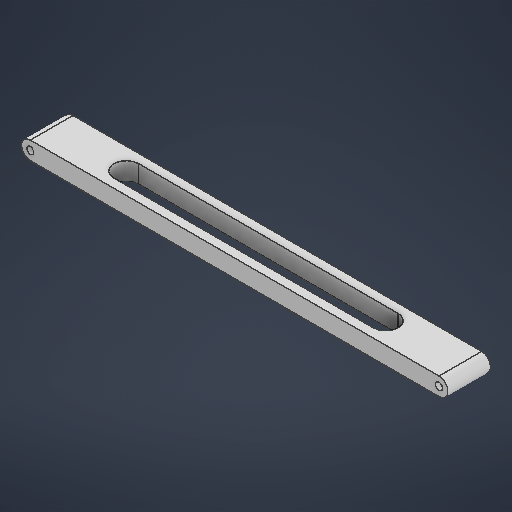
# Autodesk Inventor part: barraBrazo2
Saved by Autodesk Inventor 2027.1 (Build 311270010, 270A)
## iProperties
Created: 2026-11-02
Part Number: barraBrazo2
Material: Genérico
Document SubType Name: Modeling
Designer: MANGEL
Density: 1 g/cm^3
Appearance: Valor por defecto
Author: MANGEL
Autodesk Inventor part; units mm, degrees
ref_plane "YZ Plane" through (0, 0, 0) normal (1, 0, 0) x (0, 1, 0)
ref_plane "XZ Plane" through (0, 0, 0) normal (0, 1, 0) x (-1, 0, 0)
ref_plane "XY Plane" through (0, 0, 0) normal (0, 0, 1) x (1, 0, 0)
sketch "Boceto1" plane through (0, 0, 0) normal (0, 0, 1) x (1, 0, 0)
  line L0 (-115, 0) -> (115, 0) construction
  line L1 (-115, -5) -> (115, -5)
  line L2 (115, 5) -> (-115, 5)
  arc A0 (-115, 5) -> (-115, -5) centre (-115, 0) ccw
  arc A1 (115, -5) -> (115, 5) centre (115, 0) ccw
  point P0 (0, 0)
  point P1 (120, 0)
  point P2 (-120, 0)
  dimension "d0" = 10
  dimension "d1" = 240
  constraints: 8 end point, 6 point on circle, 4 tangent, 2 centre point, 1 horizontal, 1 midpoint, 1 parallel
  measures "d0" distance between parallel lines of L1 L2
  measures "d1" distance of point (120, 0) point (-120, 0)
extrude "Extrusión1" add sketch "Boceto1" along normal blind 24
sketch "Boceto2" plane through (-115, 5, 0) normal (0, 1, 0) x (1, 0, 0)
  line L0 (42, -12) -> (188, -12) construction
  line L1 (42, -19) -> (188, -19)
  line L2 (188, -5) -> (42, -5)
  arc A0 (42, -5) -> (42, -19) centre (42, -12) ccw
  arc A1 (188, -19) -> (188, -5) centre (188, -12) ccw
  line L3 (230, 0) -> (0, 0) projected
  line L4 (230, 0) -> (230, -24) projected
  point P0 (115, 0)
  point P1 (115, -12)
  point P2 (195, -12)
  point P3 (35, -12)
  point P4 (115, 0)
  point P5 (230, -12)
  dimension "d4" = 14
  dimension "d5" = 160
  constraints: 8 end point, 6 point on circle, 4 tangent, 3 midpoint, 2 centre point, 1 horizontal, 1 horizontal alignment, 1 parallel, 1 vertical alignment
  measures "d4" distance between parallel lines of L1 L2
  measures "d5" distance of point (195, -12) point (35, -12)
extrude "Extrusión2" cut sketch "Boceto2" against normal blind 24
sketch "Boceto3" plane through (0, 0, 24) normal (0, 0, 1) x (1, 0, 0)
  arc A0 (115, -5) -> (115, 5) centre (115, 0) ccw projected
  circle A1 centre (115, 0) radius 2
  arc A2 (-115, 5) -> (-115, -5) centre (-115, 0) ccw projected
  circle A3 centre (-115, 0) radius 2
  point P0 (0, 0)
  dimension "d8" = 4
  dimension "d9" = 4
  constraints: 2 centre point, 2 coincident
  measures "d8" diameter of A3
  measures "d9" diameter of A1
extrude "Extrusión3" cut sketch "Boceto3" against normal through all
